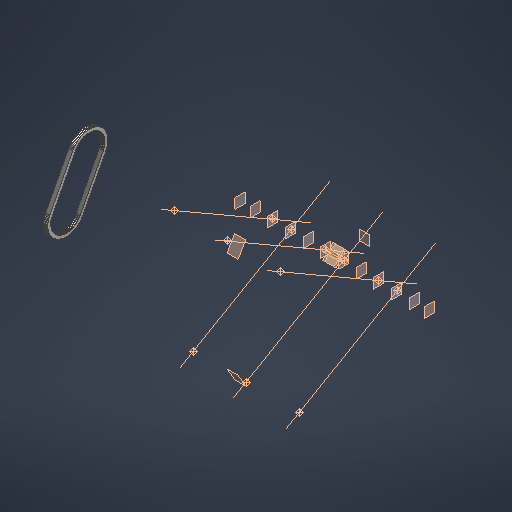
# Autodesk Inventor part: Timing_Chain_Secondary_A_SIMPLIFIED
Saved by Autodesk Inventor 2027.1 (Build 311270010, 270A)
## iProperties
Created: 2026-10-17
Part Number: Timing_Chain_Secondary_A_SIMPLIFIED
Material: Steel, Carbon
Document SubType Name: Modeling
Designer: kashyap
Density: 7.85 g/cm^3
Appearance: Semi-Polished
Material_Status: Assumed for this reconstruction
Author: kashyap
Autodesk Inventor part; units mm, degrees
ref_plane "YZ Plane" through (0, 0, 0) normal (1, 0, 0) x (0, 1, 0)
derived "V6_Engine_Master.ipt"
ref_plane "Bank_A_Plane" through (0, 0, 0) normal (0, 0.8660254, -0.5) x (-1, 0, 0)
ref_plane "Bank_B_Plane" through (0, 0, 0) normal (0, 0.8660254, 0.5) x (-1, 0, 0)
ref_plane "Bank_A_Perp_Plane" through (0, 0, 0) normal (0, 0.5, 0.8660254) x (-1, 0, 0)
ref_plane "Bank_B_Perp_Plane" through (0, 0, 0) normal (0, -0.5, 0.8660254) x (-1, 0, 0)
ref_plane "Bank_A_Deck_Plane" through (0, 112.9, 195.5485) normal (0, 0.5, 0.8660254) x (-1, 0, 0)
ref_plane "Bank_B_Deck_Plane" through (0, -112.9, 195.5485) normal (0, -0.5, 0.8660254) x (-1, 0, 0)
ref_plane "Cyl_A1_Station_Plane" through (-123.8, 0, 0) normal (1, 0, 0) x (0, 1, 0)
ref_plane "Cyl_A2_Station_Plane" through (-18.3, 0, 0) normal (1, 0, 0) x (0, 1, 0)
ref_plane "Cyl_A3_Station_Plane" through (87.2, 0, 0) normal (1, 0, 0) x (0, 1, 0)
ref_plane "Cyl_B1_Station_Plane" through (-87.2, 0, 0) normal (1, 0, 0) x (0, 1, 0)
ref_plane "Cyl_B2_Station_Plane" through (18.3, 0, 0) normal (1, 0, 0) x (0, 1, 0)
ref_plane "Cyl_B3_Station_Plane" through (123.8, 0, 0) normal (1, 0, 0) x (0, 1, 0)
ref_plane "Main_Bearing_Station_1" through (-158.25, 0, 0) normal (1, 0, 0) x (0, 1, 0)
ref_plane "Main_Bearing_Station_2" through (-52.75, 0, 0) normal (1, 0, 0) x (0, 1, 0)
ref_plane "Main_Bearing_Station_3" through (52.75, 0, 0) normal (1, 0, 0) x (0, 1, 0)
ref_plane "Main_Bearing_Station_4" through (158.25, 0, 0) normal (1, 0, 0) x (0, 1, 0)
ref_plane "Front_Interface" through (-188.25, 0, 0) normal (1, 0, 0) x (0, 1, 0)
ref_plane "Rear_Interface" through (188.25, 0, 0) normal (1, 0, 0) x (0, 1, 0)
ref_plane "Oil_Pan_Plane" through (0, 0, -60) normal (0, 0, 1) x (1, 0, 0)
ref_plane "Primary_Sprocket_Plane" through (-193.75, 0, 0) normal (1, 0, 0) x (0, 1, 0)
ref_plane "Secondary_Sprocket_Plane" through (-203.75, 0, 0) normal (1, 0, 0) x (0, 1, 0)
sketch "SK_Chain" plane through (-203.75, 0, 0) normal (1, 0, 0) x (0, 1, 0)
  line L0 (99.1395, 334.29) -> (99.1901, 332.3574)
  line L1 (99.1901, 332.3574) -> (99.3418, 330.4301)
  line L2 (99.3418, 330.4301) -> (99.5941, 328.5134)
  line L3 (99.5941, 328.5134) -> (99.9464, 326.6126)
  line L4 (99.9464, 326.6126) -> (100.3977, 324.7328)
  line L5 (100.3977, 324.7328) -> (100.9468, 322.8792)
  line L6 (100.9468, 322.8792) -> (101.5921, 321.0568)
  line L7 (101.5921, 321.0568) -> (102.3319, 319.2708)
  line L8 (102.3319, 319.2708) -> (103.1642, 317.5258)
  line L9 (103.1642, 317.5258) -> (104.0867, 315.8269)
  line L10 (104.0867, 315.8269) -> (105.0968, 314.1785)
  line L11 (105.0968, 314.1785) -> (106.1918, 312.5853)
  line L12 (106.1918, 312.5853) -> (107.3687, 311.0516)
  line L13 (107.3687, 311.0516) -> (108.6242, 309.5816)
  line L14 (108.6242, 309.5816) -> (109.9549, 308.1792)
  line L15 (109.9549, 308.1792) -> (111.3572, 306.8485)
  line L16 (111.3572, 306.8485) -> (112.8273, 305.593)
  line L17 (112.8273, 305.593) -> (114.361, 304.4161)
  line L18 (114.361, 304.4161) -> (115.9542, 303.3211)
  line L19 (115.9542, 303.3211) -> (117.6026, 302.311)
  line L20 (117.6026, 302.311) -> (119.3015, 301.3885)
  line L21 (119.3015, 301.3885) -> (207.8675, 255.3528)
  line L22 (207.8675, 255.3528) -> (209.6124, 254.5205)
  line L23 (209.6124, 254.5205) -> (211.3984, 253.7807)
  line L24 (211.3984, 253.7807) -> (213.2208, 253.1354)
  line L25 (213.2208, 253.1354) -> (215.0744, 252.5863)
  line L26 (215.0744, 252.5863) -> (216.9542, 252.135)
  line L27 (216.9542, 252.135) -> (218.8551, 251.7827)
  line L28 (218.8551, 251.7827) -> (220.7717, 251.5303)
  line L29 (220.7717, 251.5303) -> (222.699, 251.3787)
  line L30 (222.699, 251.3787) -> (224.6316, 251.3281)
  line L31 (224.6316, 251.3281) -> (226.5641, 251.3787)
  line L32 (226.5641, 251.3787) -> (228.4914, 251.5303)
  line L33 (228.4914, 251.5303) -> (230.4081, 251.7827)
  line L34 (230.4081, 251.7827) -> (232.309, 252.135)
  line L35 (232.309, 252.135) -> (234.1888, 252.5863)
  line L36 (234.1888, 252.5863) -> (236.0424, 253.1354)
  line L37 (236.0424, 253.1354) -> (237.8647, 253.7807)
  line L38 (237.8647, 253.7807) -> (239.6508, 254.5205)
  line L39 (239.6508, 254.5205) -> (241.3957, 255.3528)
  line L40 (241.3957, 255.3528) -> (243.0947, 256.2752)
  line L41 (243.0947, 256.2752) -> (244.743, 257.2853)
  line L42 (244.743, 257.2853) -> (246.3362, 258.3803)
  line L43 (246.3362, 258.3803) -> (247.87, 259.5572)
  line L44 (247.87, 259.5572) -> (249.34, 260.8127)
  line L45 (249.34, 260.8127) -> (250.7423, 262.1435)
  line L46 (250.7423, 262.1435) -> (252.0731, 263.5458)
  line L47 (252.0731, 263.5458) -> (253.3286, 265.0158)
  line L48 (253.3286, 265.0158) -> (254.5055, 266.5496)
  line L49 (254.5055, 266.5496) -> (255.6005, 268.1428)
  line L50 (255.6005, 268.1428) -> (256.6106, 269.7911)
  line L51 (256.6106, 269.7911) -> (257.533, 271.4901)
  line L52 (257.533, 271.4901) -> (258.3653, 273.235)
  line L53 (258.3653, 273.235) -> (259.1051, 275.0211)
  line L54 (259.1051, 275.0211) -> (259.7504, 276.8434)
  line L55 (259.7504, 276.8434) -> (260.2995, 278.697)
  line L56 (260.2995, 278.697) -> (260.7508, 280.5768)
  line L57 (260.7508, 280.5768) -> (261.1031, 282.4777)
  line L58 (261.1031, 282.4777) -> (261.3554, 284.3944)
  line L59 (261.3554, 284.3944) -> (261.5071, 286.3216)
  line L60 (261.5071, 286.3216) -> (261.5577, 288.2542)
  line L61 (261.5577, 288.2542) -> (261.5071, 290.1868)
  line L62 (261.5071, 290.1868) -> (261.3554, 292.114)
  line L63 (261.3554, 292.114) -> (261.1031, 294.0307)
  line L64 (261.1031, 294.0307) -> (260.7508, 295.9316)
  line L65 (260.7508, 295.9316) -> (260.2995, 297.8114)
  line L66 (260.2995, 297.8114) -> (259.7504, 299.665)
  line L67 (259.7504, 299.665) -> (259.1051, 301.4874)
  line L68 (259.1051, 301.4874) -> (258.3653, 303.2734)
  line L69 (258.3653, 303.2734) -> (257.533, 305.0183)
  line L70 (257.533, 305.0183) -> (256.6106, 306.7173)
  line L71 (256.6106, 306.7173) -> (255.6005, 308.3656)
  line L72 (255.6005, 308.3656) -> (254.5055, 309.9589)
  line L73 (254.5055, 309.9589) -> (253.3286, 311.4926)
  line L74 (253.3286, 311.4926) -> (252.0731, 312.9626)
  line L75 (252.0731, 312.9626) -> (250.7423, 314.3649)
  line L76 (250.7423, 314.3649) -> (249.34, 315.6957)
  line L77 (249.34, 315.6957) -> (247.87, 316.9512)
  line L78 (247.87, 316.9512) -> (246.3362, 318.1281)
  line L79 (246.3362, 318.1281) -> (244.743, 319.2231)
  line L80 (244.743, 319.2231) -> (243.0947, 320.2332)
  line L81 (243.0947, 320.2332) -> (241.3957, 321.1556)
  line L82 (241.3957, 321.1556) -> (152.8298, 367.1914)
  line L83 (152.8298, 367.1914) -> (151.0849, 368.0237)
  line L84 (151.0849, 368.0237) -> (149.2988, 368.7635)
  line L85 (149.2988, 368.7635) -> (147.4765, 369.4088)
  line L86 (147.4765, 369.4088) -> (145.6229, 369.9579)
  line L87 (145.6229, 369.9579) -> (143.743, 370.4092)
  line L88 (143.743, 370.4092) -> (141.8422, 370.7615)
  line L89 (141.8422, 370.7615) -> (139.9255, 371.0138)
  line L90 (139.9255, 371.0138) -> (137.9982, 371.1655)
  line L91 (137.9982, 371.1655) -> (136.0657, 371.2161)
  line L92 (136.0657, 371.2161) -> (134.1331, 371.1655)
  line L93 (134.1331, 371.1655) -> (132.2058, 371.0138)
  line L94 (132.2058, 371.0138) -> (130.2891, 370.7615)
  line L95 (130.2891, 370.7615) -> (128.3883, 370.4092)
  line L96 (128.3883, 370.4092) -> (126.5085, 369.9579)
  line L97 (126.5085, 369.9579) -> (124.6549, 369.4088)
  line L98 (124.6549, 369.4088) -> (122.8325, 368.7635)
  line L99 (122.8325, 368.7635) -> (121.0464, 368.0237)
  line L100 (121.0464, 368.0237) -> (119.3015, 367.1914)
  line L101 (119.3015, 367.1914) -> (117.6026, 366.2689)
  line L102 (117.6026, 366.2689) -> (115.9542, 365.2588)
  line L103 (115.9542, 365.2588) -> (114.361, 364.1638)
  line L104 (114.361, 364.1638) -> (112.8273, 362.987)
  line L105 (112.8273, 362.987) -> (111.3572, 361.7314)
  line L106 (111.3572, 361.7314) -> (109.9549, 360.4007)
  line L107 (109.9549, 360.4007) -> (108.6242, 358.9984)
  line L108 (108.6242, 358.9984) -> (107.3687, 357.5283)
  line L109 (107.3687, 357.5283) -> (106.1918, 355.9946)
  line L110 (106.1918, 355.9946) -> (105.0968, 354.4014)
  line L111 (105.0968, 354.4014) -> (104.0867, 352.753)
  line L112 (104.0867, 352.753) -> (103.1642, 351.0541)
  line L113 (103.1642, 351.0541) -> (102.3319, 349.3092)
  line L114 (102.3319, 349.3092) -> (101.5921, 347.5231)
  line L115 (101.5921, 347.5231) -> (100.9468, 345.7008)
  line L116 (100.9468, 345.7008) -> (100.3977, 343.8472)
  line L117 (100.3977, 343.8472) -> (99.9464, 341.9673)
  line L118 (99.9464, 341.9673) -> (99.5941, 340.0665)
  line L119 (99.5941, 340.0665) -> (99.3418, 338.1498)
  line L120 (99.3418, 338.1498) -> (99.1901, 336.2225)
  line L121 (99.1901, 336.2225) -> (99.1395, 334.29)
  line L122 (105.1395, 334.29) -> (105.1819, 332.6714)
  line L123 (105.1819, 332.6714) -> (105.3089, 331.0573)
  line L124 (105.3089, 331.0573) -> (105.5203, 329.4521)
  line L125 (105.5203, 329.4521) -> (105.8153, 327.8601)
  line L126 (105.8153, 327.8601) -> (106.1933, 326.2857)
  line L127 (106.1933, 326.2857) -> (106.6531, 324.7333)
  line L128 (106.6531, 324.7333) -> (107.1936, 323.207)
  line L129 (107.1936, 323.207) -> (107.8132, 321.7112)
  line L130 (107.8132, 321.7112) -> (108.5103, 320.2498)
  line L131 (108.5103, 320.2498) -> (109.2828, 318.8269)
  line L132 (109.2828, 318.8269) -> (110.1288, 317.4464)
  line L133 (110.1288, 317.4464) -> (111.0459, 316.112)
  line L134 (111.0459, 316.112) -> (112.0315, 314.8275)
  line L135 (112.0315, 314.8275) -> (113.0831, 313.5963)
  line L136 (113.0831, 313.5963) -> (114.1976, 312.4219)
  line L137 (114.1976, 312.4219) -> (115.372, 311.3074)
  line L138 (115.372, 311.3074) -> (116.6032, 310.2558)
  line L139 (116.6032, 310.2558) -> (117.8877, 309.2702)
  line L140 (117.8877, 309.2702) -> (119.2221, 308.3531)
  line L141 (119.2221, 308.3531) -> (120.6026, 307.5071)
  line L142 (120.6026, 307.5071) -> (122.0255, 306.7346)
  line L143 (122.0255, 306.7346) -> (210.5914, 260.6988)
  line L144 (210.5914, 260.6988) -> (212.0528, 260.0018)
  line L145 (212.0528, 260.0018) -> (213.5486, 259.3822)
  line L146 (213.5486, 259.3822) -> (215.0749, 258.8417)
  line L147 (215.0749, 258.8417) -> (216.6273, 258.3818)
  line L148 (216.6273, 258.3818) -> (218.2017, 258.0039)
  line L149 (218.2017, 258.0039) -> (219.7937, 257.7088)
  line L150 (219.7937, 257.7088) -> (221.3989, 257.4975)
  line L151 (221.3989, 257.4975) -> (223.013, 257.3704)
  line L152 (223.013, 257.3704) -> (224.6316, 257.3281)
  line L153 (224.6316, 257.3281) -> (226.2501, 257.3704)
  line L154 (226.2501, 257.3704) -> (227.8642, 257.4975)
  line L155 (227.8642, 257.4975) -> (229.4695, 257.7088)
  line L156 (229.4695, 257.7088) -> (231.0615, 258.0039)
  line L157 (231.0615, 258.0039) -> (232.6359, 258.3818)
  line L158 (232.6359, 258.3818) -> (234.1883, 258.8417)
  line L159 (234.1883, 258.8417) -> (235.7145, 259.3822)
  line L160 (235.7145, 259.3822) -> (237.2104, 260.0018)
  line L161 (237.2104, 260.0018) -> (238.6718, 260.6988)
  line L162 (238.6718, 260.6988) -> (240.0947, 261.4714)
  line L163 (240.0947, 261.4714) -> (241.4752, 262.3174)
  line L164 (241.4752, 262.3174) -> (242.8095, 263.2344)
  line L165 (242.8095, 263.2344) -> (244.094, 264.2201)
  line L166 (244.094, 264.2201) -> (245.3252, 265.2716)
  line L167 (245.3252, 265.2716) -> (246.4997, 266.3861)
  line L168 (246.4997, 266.3861) -> (247.6142, 267.5606)
  line L169 (247.6142, 267.5606) -> (248.6657, 268.7918)
  line L170 (248.6657, 268.7918) -> (249.6514, 270.0763)
  line L171 (249.6514, 270.0763) -> (250.5684, 271.4106)
  line L172 (250.5684, 271.4106) -> (251.4144, 272.7911)
  line L173 (251.4144, 272.7911) -> (252.187, 274.214)
  line L174 (252.187, 274.214) -> (252.884, 275.6754)
  line L175 (252.884, 275.6754) -> (253.5036, 277.1713)
  line L176 (253.5036, 277.1713) -> (254.0441, 278.6975)
  line L177 (254.0441, 278.6975) -> (254.5039, 280.2499)
  line L178 (254.5039, 280.2499) -> (254.8819, 281.8243)
  line L179 (254.8819, 281.8243) -> (255.177, 283.4163)
  line L180 (255.177, 283.4163) -> (255.3883, 285.0215)
  line L181 (255.3883, 285.0215) -> (255.5153, 286.6357)
  line L182 (255.5153, 286.6357) -> (255.5577, 288.2542)
  line L183 (255.5577, 288.2542) -> (255.5153, 289.8728)
  line L184 (255.5153, 289.8728) -> (255.3883, 291.4869)
  line L185 (255.3883, 291.4869) -> (255.177, 293.0921)
  line L186 (255.177, 293.0921) -> (254.8819, 294.6841)
  line L187 (254.8819, 294.6841) -> (254.5039, 296.2585)
  line L188 (254.5039, 296.2585) -> (254.0441, 297.8109)
  line L189 (254.0441, 297.8109) -> (253.5036, 299.3371)
  line L190 (253.5036, 299.3371) -> (252.884, 300.833)
  line L191 (252.884, 300.833) -> (252.187, 302.2944)
  line L192 (252.187, 302.2944) -> (251.4144, 303.7173)
  line L193 (251.4144, 303.7173) -> (250.5684, 305.0978)
  line L194 (250.5684, 305.0978) -> (249.6514, 306.4321)
  line L195 (249.6514, 306.4321) -> (248.6657, 307.7167)
  line L196 (248.6657, 307.7167) -> (247.6142, 308.9478)
  line L197 (247.6142, 308.9478) -> (246.4997, 310.1223)
  line L198 (246.4997, 310.1223) -> (245.3252, 311.2368)
  line L199 (245.3252, 311.2368) -> (244.094, 312.2883)
  line L200 (244.094, 312.2883) -> (242.8095, 313.274)
  line L201 (242.8095, 313.274) -> (241.4752, 314.1911)
  line L202 (241.4752, 314.1911) -> (240.0947, 315.037)
  line L203 (240.0947, 315.037) -> (238.6718, 315.8096)
  line L204 (238.6718, 315.8096) -> (150.1058, 361.8454)
  line L205 (150.1058, 361.8454) -> (148.6445, 362.5424)
  line L206 (148.6445, 362.5424) -> (147.1486, 363.162)
  line L207 (147.1486, 363.162) -> (145.6224, 363.7025)
  line L208 (145.6224, 363.7025) -> (144.0699, 364.1623)
  line L209 (144.0699, 364.1623) -> (142.4956, 364.5403)
  line L210 (142.4956, 364.5403) -> (140.9036, 364.8354)
  line L211 (140.9036, 364.8354) -> (139.2983, 365.0467)
  line L212 (139.2983, 365.0467) -> (137.6842, 365.1737)
  line L213 (137.6842, 365.1737) -> (136.0657, 365.2161)
  line L214 (136.0657, 365.2161) -> (134.4471, 365.1737)
  line L215 (134.4471, 365.1737) -> (132.833, 365.0467)
  line L216 (132.833, 365.0467) -> (131.2277, 364.8354)
  line L217 (131.2277, 364.8354) -> (129.6358, 364.5403)
  line L218 (129.6358, 364.5403) -> (128.0614, 364.1623)
  line L219 (128.0614, 364.1623) -> (126.509, 363.7025)
  line L220 (126.509, 363.7025) -> (124.9827, 363.162)
  line L221 (124.9827, 363.162) -> (123.4869, 362.5424)
  line L222 (123.4869, 362.5424) -> (122.0255, 361.8454)
  line L223 (122.0255, 361.8454) -> (120.6026, 361.0728)
  line L224 (120.6026, 361.0728) -> (119.2221, 360.2268)
  line L225 (119.2221, 360.2268) -> (117.8877, 359.3097)
  line L226 (117.8877, 359.3097) -> (116.6032, 358.3241)
  line L227 (116.6032, 358.3241) -> (115.372, 357.2726)
  line L228 (115.372, 357.2726) -> (114.1976, 356.1581)
  line L229 (114.1976, 356.1581) -> (113.0831, 354.9836)
  line L230 (113.0831, 354.9836) -> (112.0315, 353.7524)
  line L231 (112.0315, 353.7524) -> (111.0459, 352.4679)
  line L232 (111.0459, 352.4679) -> (110.1288, 351.1336)
  line L233 (110.1288, 351.1336) -> (109.2828, 349.753)
  line L234 (109.2828, 349.753) -> (108.5103, 348.3301)
  line L235 (108.5103, 348.3301) -> (107.8132, 346.8688)
  line L236 (107.8132, 346.8688) -> (107.1936, 345.3729)
  line L237 (107.1936, 345.3729) -> (106.6531, 343.8467)
  line L238 (106.6531, 343.8467) -> (106.1933, 342.2942)
  line L239 (106.1933, 342.2942) -> (105.8153, 340.7199)
  line L240 (105.8153, 340.7199) -> (105.5203, 339.1279)
  line L241 (105.5203, 339.1279) -> (105.3089, 337.5226)
  line L242 (105.3089, 337.5226) -> (105.1819, 335.9085)
  line L243 (105.1819, 335.9085) -> (105.1395, 334.29)
  constraints: 488 end point
extrude "Chain_Band_SIMPLIFIED" add sketch "SK_Chain" along normal mid plane 8
body "Solid2"
